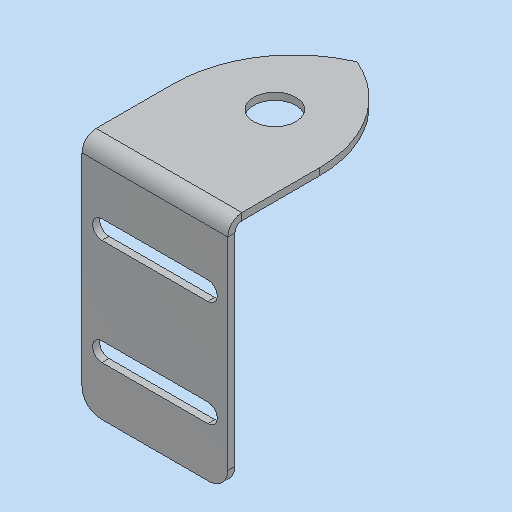
# Autodesk Inventor part: MM0861AN200_G22_219
Saved by Autodesk Inventor 2023.3 (Build 273359000, 359)
## iProperties
RuleStatus: InUse
Created: 2021-05-06
Part Number: MM0861AN200_G22_219
Material: 3.3535 AlMg3 - AW 5754 (Blech)
Description: =<RBPARTNOTITLE2>
Document SubType Name: Blech
Designer: frt9bw
Mass: 75.3672 g
Surface Area: 208.038 cm^2
Volume: 27.9241 cm^3
Density: 2.699 g/cm^3
Sheet Metal Rule: Standard_mm
Appearance: Aluminium AnP
Flat Pattern Width: 6.2 cm
Flat Pattern Length: 18.0786 cm
Flat Pattern Area: 112.087 cm^2
Sheet Metal Width: 62,000 mm
Sheet Metal Length: 180,786 mm
Sheet Metal Area: 11208,722 mm^2
Vendor: ASW
AnP_Kategorie: 1
AnP_Material: =<Material>
MaxAbmaße: 100 x 86 x 62 (FM)
AnP_TemplVers: 20200821
RBDOCUMENTTYPE: DRF
RBDOCUMENTVERSION: 00
RBDRAWINGMAINSCALE: 1:1
RBDRAWINGMISSINGSPEC: --
RBDRAWINGVOLUME: --
RBDSV1: 0850
RBGBEDGESIN1: +0,5
RBGBEDGESIN2: +0,2
RBGBEDGESOUT1: -0,3
RBGBEDGESOUT2: -0,1
RBMATERIAL: =<Material>
RBMATMEETS: --
RBMATNO: =<Part Number>
RBPARTMADEOF: 100 x 86 x 62 (FM)
RBPARTNO: SIEHE MNR
RBPARTNOTITLE1: manufactured part
RBPARTNOTITLE2: Anfertigungsteil
RBPARTSAFETYINDICATOR: --
RBSURFACE: --
RBSURFACE2: eloxiert E6/EV1 aluminiumfarbig
RBZEDGESNORM: ISO13715:2002-06
RBZGENDIMCLASS: m
RBZGENDIMNORM: ISO 2768-1:1989-11
RBZGENGEOCLASS: H
RBZGENGEONORM: ISO 2768-2:1989-11
RBZSURFACENORM: ISO13D2:2002-02
RBZTOLERANCENORM: ISO 14405-1:2010-12
Author: frt9bw
Keywords: =<RBPARTMADEOF>
Comments: =<RBSURFACE2>
Revision Number: 01
Autodesk Inventor part; units mm, degrees
ref_plane "XY Plane" through (0, 0, 0) normal (0, 0, 1) x (1, 0, 0)
sketch "Skizze1" plane through (0, 0, 0) normal (0, 0, 1) x (1, 0, 0)
  line L0 (0, 0) -> (62, 0)
  line L1 (62, 0) -> (62, -80)
  line L2 (62, -80) -> (0, -80)
  line L3 (0, -80) -> (0, 0)
  dimension "d1" = 62
  dimension "d2" = 80
  measures "d1" distance of L1.end L2.end
  measures "d2" distance of L0.end L1.end
extrude "Grobblech1" add sketch "Skizze1" along normal blind 3
sketch "Skizze2" plane through (0, 0, 3) normal (0, 0, 1) x (1, 0, 0)
  arc A0 (62, -47.178) -> (31, 0.0004) centre (10.6, -47.178) ccw
  arc A1 (31, 0.0004) -> (0, -47.178) centre (51.4, -47.178) ccw
  line L0 (0, -80) -> (0, 0) projected
  line L1 (62, 0) -> (62, -80) projected
  line L2 (0, 0) -> (62, 0) projected
  point P0 (31.0009, 0)
  point P1 (30.9991, 0)
  dimension "d4" = 102.8
  dimension "d5" = 102.8
  dimension "d6" = 47.178
  constraints: 4 point on circle, 2 centre point, 2 point on line, 2 tangent, 1 horizontal alignment
  measures "d4" diameter of A0
  measures "d5" diameter of A1
  measures "d6" distance from line of L2 A0.centre
extrude "Extrusion1" cut sketch "Skizze2" against normal through all
sketch "Skizze3" plane through (0, 0, 3) normal (0, 0, 1) x (1, 0, 0)
  arc A0 (62, -47.178) -> (31.0009, 0) centre (10.6, -47.178) ccw projected
  line L0 (30.9991, 0) -> (31.0009, 0) projected
  arc A1 (30.9991, 0) -> (0, -47.178) centre (51.4, -47.178) ccw projected
  line L1 (0, -80) -> (0, -47.178) projected
  line L2 (62, -80) -> (0, -80) projected
  line L3 (62, -47.178) -> (62, -80) projected
  point P0 (0, 0)
  point P1 (31, -35)
  dimension "d9" = 31
  dimension "d10" = 35
  measures "d9" distance from line of point (31, -35) L1
  measures "d10" distance of point (31, -35) L0.start
hole "Bohrung1" at (31, -35, 3) direction (0, 0, -1) diameter 18 depth 3 tip angle 118
sketch "Skizze4" plane through (0, -83, -3) normal (0, -1, 0) x (1, 0, 0)
  line L0 (62, 0) -> (0, 0)
  line L1 (0, 0) -> (0, -94)
  line L2 (0, -94) -> (62, -94)
  line L3 (62, -94) -> (62, 0)
  constraints: 6 end point, 1 horizontal, 1 perpendicular, 1 vertical
edge flange "Lasche1" height 100 angle 90 thickness 3 bend radius 3 thickness toward (0, -1, 0) relief tear relief width 3 relief depth 1.5 edges at (31, -80, 0) wall of the first edge with corners at (62, -83, -3) (0, -83, -3) (0, -83, -97) (62, -83, -97)
bend "Biegung1"
corner "Ecke1"
sketch "Skizze5" plane through (0, -83, -97) normal (0, 1, 0) x (1, 0, 0)
  line L0 (8.5, -25) -> (53.5, -25) construction
  line L1 (8.5, -29) -> (53.5, -29)
  line L2 (53.5, -21) -> (8.5, -21)
  arc A0 (8.5, -21) -> (8.5, -29) centre (8.5, -25) ccw
  arc A1 (53.5, -29) -> (53.5, -21) centre (53.5, -25) ccw
  line L3 (8.5, -70) -> (53.5, -70) construction
  line L4 (8.5, -74) -> (53.5, -74)
  line L5 (53.5, -66) -> (8.5, -66)
  arc A2 (8.5, -66) -> (8.5, -74) centre (8.5, -70) ccw
  arc A3 (53.5, -74) -> (53.5, -66) centre (53.5, -70) ccw
  line L6 (62, 0) -> (0, 0) projected
  line L7 (0, 0) -> (0, -94) projected
  point P0 (0, -97)
  point P1 (31, -25)
  point P2 (31, -70)
  dimension "d28" = 8
  dimension "d29" = 8
  dimension "d30" = 45
  dimension "d31" = 25
  dimension "d32" = 45
  dimension "d33" = 31
  constraints: 16 end point, 8 point on circle, 8 tangent, 4 centre point, 3 parallel, 2 midpoint, 2 vertical alignment, 1 horizontal
  measures "d28" diameter of A1
  measures "d29" diameter of A3
  measures "d30" distance of L0.end L0.start
  measures "d31" distance from line of L6 point (31, -25)
  measures "d32" distance of point (31, -25) point (31, -70)
  measures "d33" distance from line of L7 point (31, -25)
extrude "Extrusion2" cut sketch "Skizze5" against normal through all
fillet "Rundung1" radius 8 2 edges at (62, -84.5, -97) (0, -84.5, -97)
ref_plane "Arbeitsebene1" through (31, 0, 0) normal (1, 0, 0) x (0, 1, 0)
ref_plane "Arbeitsebene2" through (0, -86, 0) normal (0, 1, 0) x (-1, 0, 0)
equation "\"d16\" = Stärke"
equation "\"d3\" = Stärke"
equation "\"d18\" = BreiteBiegungsfreistellung"
equation "\"d19\" = TiefeBiegungsfreistellung"
equation "\"d20\" = MinimalRest"
equation "\"d21\" = Übergangsradius"
equation "\"d24\" = Biegeradius"
equation "\"d25\" = GrößeEckenfreistellung"
equation "\"d26\" = Abstandsgröße"
equation "\"d27\" = JacobiRadiusGröße"
equation "\"Biegeradius\" = Stärke"
equation "\"BreiteBiegungsfreistellung\" = Stärke"
equation "\"TiefeBiegungsfreistellung\" = 0.5 * Stärke"
equation "\"GrößeEckenfreistellung\" = 4 * Stärke"
equation "\"MinimalRest\" = 2 * Stärke"
equation "\"Übergangsradius\" = Biegeradius"
equation "\"JacobiRadiusGröße\" = Biegeradius"
equation "\"Abstandsgröße\" = Stärke"
equation "\"Stärke\" = 3"
